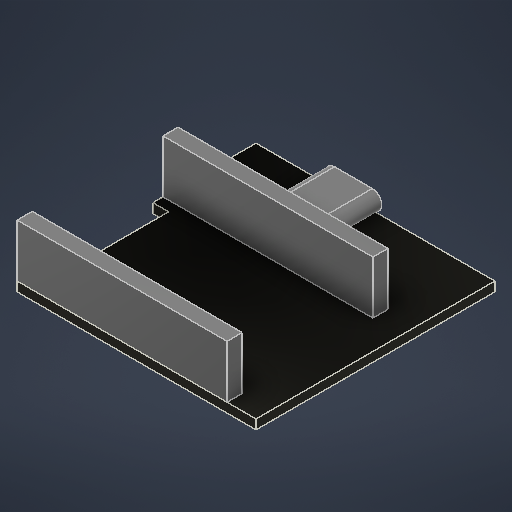
# Autodesk Inventor part: ETH32 uploader
Saved by Autodesk Inventor 2027.1 (Build 311270010, 270A)
## iProperties
Created: 2026-09-27
Part Number: ETH32 uploader
Material: 열가소성 수지
Document SubType Name: Modeling
Designer: work
Density: 1.28 g/cm^3
Appearance: 매끄러움 - 검은색
Author: work
Autodesk Inventor part; units mm, degrees
ref_plane "YZ Plane" through (0, 0, 0) normal (1, 0, 0) x (0, 1, 0)
ref_plane "XZ Plane" through (0, 0, 0) normal (0, 1, 0) x (-1, 0, 0)
ref_plane "XY Plane" through (0, 0, 0) normal (0, 0, 1) x (1, 0, 0)
sketch "스케치1" plane through (0, 0, 0) normal (0, 1, 0) x (-1, 0, 0)
  line L0 (0, 0) -> (38, 0)
  line L1 (38, 0) -> (38, -38)
  line L2 (38, -38) -> (0, -38)
  line L3 (0, -38) -> (0, 0)
  line L4 (38, -4) -> (35.5, -4)
  line L5 (35.5, -4) -> (35.5, -21.6)
  line L6 (35.5, -21.6) -> (38, -21.6)
  line L7 (38, -21.6) -> (38, -4)
  point P0 (38, -21.6)
  dimension "d0" = 38
  dimension "d1" = 38
  dimension "d2" = 2.5
  dimension "d3" = 17.6
  dimension "d4" = 4
  constraints: 16 end point, 4 parallel, 2 horizontal, 2 perpendicular, 1 point on line
  measures "d0" distance of L1.end L2.end
  measures "d1" distance of L0.end L1.end
  measures "d2" distance of L6.end L5.end
  measures "d3" distance of L5.end L4.end
  measures "d4" distance from line of L0 L4.start
extrude "돌출1" add sketch "스케치1" along normal blind 1.5 contours L0 L1 L4 L5 L6 L2 L3
sketch "스케치2" plane through (0, 1.5, 0) normal (0, 1, 0) x (1, 0, 0)
  line L0 (-35.5, 21.6) -> (-35.5, 4) projected
  line L1 (-35.5, 12.8) -> (0, 12.8) construction
  line L2 (0, 0) -> (0, 38) projected
  line L3 (-38, 4) -> (-38, 0) projected
  line L4 (-38, 0) -> (-4.6, 0)
  line L5 (-4.6, 0) -> (-4.6, 2.4)
  line L6 (-4.6, 2.4) -> (-38, 2.4)
  line L7 (-38, 2.4) -> (-38, 0)
  line L8 (-38, 25.6) -> (-4.6, 25.6)
  line L9 (-4.6, 25.6) -> (-4.6, 23.2)
  line L10 (-4.6, 23.2) -> (-38, 23.2)
  line L11 (0, 0) -> (0, 38) projected
  line L12 (0, 38) -> (-38, 38) projected
  line L13 (-38, 38) -> (-38, 21.6) projected
  line L14 (-38, 21.6) -> (-35.5, 21.6) projected
  line L15 (-35.5, 21.6) -> (-35.5, 4) projected
  line L16 (-35.5, 4) -> (-38, 4) projected
  line L17 (-38, 4) -> (-38, 0) projected
  line L18 (-38, 0) -> (0, 0) projected
  dimension "d7" = 2.4
  dimension "d9" = 33.4
  constraints: 16 end point, 4 symmetric about line, 2 horizontal, 2 parallel, 1 midpoint, 1 perpendicular, 1 point on line
  measures "d7" distance of L5.end L4.end
  measures "d9" distance of L3.end L4.end
extrude "돌출2" add sketch "스케치2" along normal blind 8.4 separate body contours L13 L8 L9 L10 | L6 L5 L4 L3
sketch "스케치3" plane through (0, 0, -38) normal (0, 0, -1) x (-1, 0, 0)
  line L0 (19.5, 3) -> (25.5, 3) construction
  line L1 (19.5, 1.5) -> (25.5, 1.5)
  line L2 (25.5, 4.5) -> (19.5, 4.5)
  arc A0 (19.5, 4.5) -> (19.5, 1.5) centre (19.5, 3) ccw
  arc A1 (25.5, 1.5) -> (25.5, 4.5) centre (25.5, 3) ccw
  line L3 (0, 1.5) -> (38, 1.5) projected
  line L4 (38, 1.5) -> (38, 9.9) projected
  line L5 (25.5, 4.3) -> (19.5, 4.3)
  arc A2 (19.5, 4.3) -> (19.5, 1.7) centre (19.5, 3) ccw
  line L6 (19.5, 1.7) -> (25.5, 1.7)
  arc A3 (25.5, 1.7) -> (25.5, 4.3) centre (25.5, 3) ccw
  point P0 (0, 0)
  point P1 (22.5, 3)
  point P2 (18, 3)
  point P3 (27, 3)
  dimension "d12" = 3
  dimension "d13" = 9
  dimension "d14" = 11
  dimension "d15" = 0.2
  constraints: 12 end point, 10 point on circle, 4 centre point, 4 tangent, 2 parallel, 1 horizontal, 1 midpoint, 1 point on line, 3 other
  measures "d12" distance between parallel lines of L1 L2
  measures "d13" distance of point (18, 3) point (27, 3)
  measures "d14" distance from line of L4 point (27, 3)
  measures "d15" radial gap between concentric circles of A1 A3
extrude "돌출3" add sketch "스케치3" against normal blind 7 separate body
sketch "스케치4" plane through (0, 0, -31) normal (0, 0, 1) x (1, 0, 0)
  arc A0 (-19.5, 1.5) -> (-19.5, 4.5) centre (-19.5, 3) ccw projected
  line L0 (-19.5, 1.5) -> (-25.5, 1.5) projected
  arc A1 (-25.5, 4.5) -> (-25.5, 1.5) centre (-25.5, 3) ccw projected
  line L1 (-25.5, 4.5) -> (-19.5, 4.5) projected
  arc A2 (-25.5, 4.3) -> (-25.5, 1.7) centre (-25.5, 3) ccw projected
  line L2 (-25.5, 1.7) -> (-19.5, 1.7) projected
  arc A3 (-19.5, 1.7) -> (-19.5, 4.3) centre (-19.5, 3) ccw projected
  line L3 (-19.5, 4.3) -> (-25.5, 4.3) projected
  point P0 (0, 0)
extrude "돌출4" add sketch "스케치4" against normal blind 0.2 contours L0 A1 L1 A0 | L3 A3 L2 A2 bodies 3
